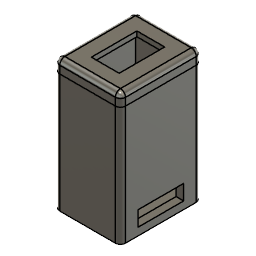
D_Case_sensor_temperatura (Autodesk Fusion 360 design; units mm, degrees)
Autodesk Fusion 360 part; units mm, degrees
sketch "Esboço1" plane through (0, 0, 0) normal (0, 1, 0) x (1, 0, 0)
  line L0 (11, -16) -> (-11, -16)
  line L1 (-13, -14) -> (-13, 14)
  line L2 (-11, 16) -> (11, 16)
  line L3 (13, 14) -> (13, -14)
  line L4 (13, -16) -> (-13, 16) construction
  line L5 (-13, -16) -> (13, 16) construction
  line L6 (10, -13) -> (-10, -13)
  line L7 (-10, -13) -> (-10, 13)
  line L8 (-10, 13) -> (10, 13)
  line L9 (10, 13) -> (10, -13)
  line L10 (10, -13) -> (-10, 13) construction
  line L11 (-10, -13) -> (10, 13) construction
  arc A0 (-11, 16) -> (-13, 14) centre (-11, 14) ccw
  arc A1 (13, 14) -> (11, 16) centre (11, 14) ccw
  arc A2 (11, -16) -> (13, -14) centre (11, -14) ccw
  arc A3 (-13, -14) -> (-11, -16) centre (-11, -14) ccw
  line L12 (0, 0) -> (-11.5, 0)
  line L13 (0, 0) -> (11.5, 0)
  line L14 (-10.75, -11.5) -> (-12.25, -11.5)
  line L15 (-12.25, -11.5) -> (-12.25, 11.5)
  line L16 (-12.25, 11.5) -> (-10.75, 11.5)
  line L17 (-10.75, 11.5) -> (-10.75, -11.5)
  line L18 (-10.75, -11.5) -> (-12.25, 11.5) construction
  line L19 (-12.25, -11.5) -> (-10.75, 11.5) construction
  line L20 (0, 0) -> (0, -14.5)
  line L21 (8.5, -15.25) -> (-8.5, -15.25)
  line L22 (-8.5, -15.25) -> (-8.5, -13.75)
  line L23 (-8.5, -13.75) -> (8.5, -13.75)
  line L24 (8.5, -13.75) -> (8.5, -15.25)
  line L25 (8.5, -15.25) -> (-8.5, -13.75) construction
  line L26 (-8.5, -15.25) -> (8.5, -13.75) construction
  line L27 (10.75, 11.5) -> (10.75, -11.5)
  line L28 (12.25, -11.5) -> (12.25, 11.5)
  line L29 (10.75, -11.5) -> (12.25, 11.5) construction
  line L30 (12.25, -11.5) -> (10.75, 11.5) construction
  line L31 (12.25, 11.5) -> (10.75, 11.5)
  line L32 (10.75, -11.5) -> (12.25, -11.5)
  line L33 (-8.5, 15.25) -> (-8.5, 13.75)
  line L34 (-8.5, 15.25) -> (8.5, 13.75) construction
  line L35 (8.5, 15.25) -> (-8.5, 13.75) construction
  line L36 (-8.5, 13.75) -> (8.5, 13.75)
  line L37 (8.5, 15.25) -> (-8.5, 15.25)
  line L38 (8.5, 13.75) -> (8.5, 15.25)
  point P0 (-11.5, 0)
  point P1 (0, -14.5)
  dimension "d1" = 26
  dimension "d2" = 32
  dimension "d3" = 20
  dimension "d4" = 26
  dimension "d5" = 2
  dimension "d6" = 2
  dimension "d7" = 11.5
  dimension "d8" = 11.5
  dimension "d9" = 1.5
  dimension "d10" = 23
  dimension "d11" = 14.5
  dimension "d12" = 17
  dimension "d13" = 1.5
  constraint horizontal L0
  constraint perpendicular L0 L1
  constraint parallel L0 L2
  constraint parallel L1 L3
  constraint coincident L4 L12.start
  constraint coincident L5 L12.start
  constraint coincident L12.start L13.start
  constraint horizontal L6
  constraint perpendicular L6 L7
  constraint parallel L6 L8
  constraint parallel L7 L9
  constraint coincident L10 L12.start
  constraint coincident L11 L12.start
  constraint coincident L4.end L2
  constraint coincident L4.end L1
  constraint tangent L2 A0
  constraint tangent L1 A0
  constraint coincident L5.end L2
  constraint coincident L5.end L3
  constraint tangent L2 A1
  constraint tangent L3 A1
  constraint coincident L4.start L3
  constraint coincident L4.start L0
  constraint tangent L3 A2
  constraint tangent L0 A2
  constraint equal A1 A2
  constraint coincident L5.start L0
  constraint coincident L5.start L1
  constraint tangent L0 A3
  constraint tangent L1 A3
  constraint equal A1 A3
  constraint perpendicular L7 L12
  constraint perpendicular L9 L13
  constraint horizontal L14
  constraint perpendicular L14 L15
  constraint parallel L14 L16
  constraint parallel L15 L17
  constraint coincident L18 P0
  constraint coincident L19 P0
  constraint coincident P0 L12.end
  constraint perpendicular L0 L20
  constraint horizontal L21
  constraint perpendicular L21 L22
  constraint parallel L21 L23
  constraint parallel L22 L24
  constraint coincident L25 P1
  constraint coincident L26 P1
  constraint coincident P1 L20.end
  constraint symmetric L14.start L20 L27.end
  constraint symmetric L14.end L20 L28.start
  constraint symmetric L15.end L20 L28.end
  constraint symmetric L16.end L20 L27.start
  constraint symmetric L12 L21.start L35.start
  constraint symmetric L12 L21.end L33.start
  constraint symmetric L12 L22.end L33.end
  constraint symmetric L12 L23.end L34.end
  measures "d1" distance of L4.end L5.end
  measures "d2" distance of L5.start L4.end
  measures "d3" distance of L7.end L8.end
  measures "d4" distance of L6.end L7.end
  measures "d5" radius of A0
  measures "d6" radius of A1
  measures "d7" distance of L12.start P0
  measures "d8" distance of L12.start L13.end
  measures "d9" distance of L15.end L16.end
  measures "d10" distance of L14.end L15.end
  measures "d11" distance of L12.start P1
  measures "d12" distance of L22.end L23.end
  measures "d13" distance of L21.end L22.end
extrude "Extrusão1" add sketch "Esboço1" against normal blind 47 contours L0 L1 L2 L3 A0 A1 A2 A3 | L14 L15 L16 L17 | L21 L22 L23 L24 | L27 L28 L31 L32 | L33 L36 L37 L38 makes body 1
sketch "Esboço2" plane through (0, 0, 0) normal (0, 1, 0) x (1, 0, 0)
extrude "Extrusão2" cut sketch "Esboço1" against normal blind 3 contours L14 L15 L16 L17 | L21 L22 L23 L24 | L27 L28 L31 L32 | L33 L36 L37 L38 bodies 1
copy_body "Corpo -> Componente1" bodies 1 removing the originals makes body 2 in component "Case_Temperatura"
ref_plane "Plano de trabalho1" through (0, 3, 0) normal (0, 1, 0) x (0, 0, 1)
sketch "Esboço3" plane through (0, 3, 0) normal (0, 1, 0) x (1, 0, 0)
ref_plane "Plano de trabalho2" through (0, 3, 0) normal (0, 1, 0) x (1, 0, 0)
sketch "Esboço4" plane through (0, 3, 0) normal (0, 1, 0) x (1, 0, 0)
extrude "Extrusão1'" add sketch "Esboço1" along normal blind 5 separate body contours L0 L1 L2 L3 A0 A1 A2 A3 | L14 L15 L16 L17 | L21 L22 L23 L24 | L27 L28 L31 L32 | L33 L36 L37 L38 makes body 3 in component "Tampa_Temperatura"
sketch "Esboço5" plane through (0, 5, 0) normal (0, 1, 0) x (-1, 0, 0)
  line L0 (10, -13) -> (-10, -13)
  line L1 (-10, -13) -> (-10, 13)
  line L2 (-10, 13) -> (10, 13)
  line L3 (10, 13) -> (10, -13)
  arc A0 (11, -16) -> (13, -14) centre (11, -14) ccw
  line L4 (13, -14) -> (13, 14)
  arc A1 (13, 14) -> (11, 16) centre (11, 14) ccw
  line L5 (11, 16) -> (-11, 16)
  arc A2 (-11, 16) -> (-13, 14) centre (-11, 14) ccw
  line L6 (-13, 14) -> (-13, -14)
  arc A3 (-13, -14) -> (-11, -16) centre (-11, -14) ccw
  line L7 (-11, -16) -> (11, -16)
extrude "Extrusão2'" add sketch "Esboço5" against normal blind 2 contours L0 L1 L2 L3 bodies 3 in component "Tampa_Temperatura"
sketch "Esboço6" plane through (0, -47, 0) normal (0, -1, 0) x (1, 0, 0)
  line L0 (10, -13) -> (-10, -13)
  line L1 (-10, -13) -> (-10, 13)
  line L2 (-10, 13) -> (10, 13)
  line L3 (10, 13) -> (10, -13)
  arc A0 (-13, -14) -> (-11, -16) centre (-11, -14) ccw
  line L4 (-11, -16) -> (11, -16)
  arc A1 (11, -16) -> (13, -14) centre (11, -14) ccw
  line L5 (13, -14) -> (13, 14)
  arc A2 (13, 14) -> (11, 16) centre (11, 14) ccw
  line L6 (11, 16) -> (-11, 16)
  arc A3 (-11, 16) -> (-13, 14) centre (-11, 14) ccw
  line L7 (-13, 14) -> (-13, -14)
extrude "Extrusão1''" add sketch "Esboço6" against normal blind 2 contours L0 L1 L2 L3 bodies 2 in component "Case_Temperatura"
extrude "Extrusão3" add sketch "Esboço1" against normal blind 2 contours L14 L15 L16 L17 | L21 L22 L23 L24 | L27 L28 L31 L32 | L33 L36 L37 L38 bodies 3 in component "Tampa_Temperatura"
sketch "Esboço7" plane through (0, 5, 0) normal (0, 1, 0) x (-1, 0, 0)
  arc A0 (11, -16) -> (13, -14) centre (11, -14) ccw
  line L0 (13, -14) -> (13, 14)
  arc A1 (13, 14) -> (11, 16) centre (11, 14) ccw
  line L1 (11, 16) -> (-11, 16)
  arc A2 (-11, 16) -> (-13, 14) centre (-11, 14) ccw
  line L2 (-13, 14) -> (-13, -14)
  arc A3 (-13, -14) -> (-11, -16) centre (-11, -14) ccw
  line L3 (-11, -16) -> (11, -16)
  line L4 (-5.5, 9) -> (5.5, 9)
  line L5 (5.5, 9) -> (5.5, -9)
  line L6 (5.5, -9) -> (-5.5, -9)
  line L7 (-5.5, -9) -> (-5.5, 9)
  line L8 (-5.5, 9) -> (5.5, -9) construction
  line L9 (5.5, 9) -> (-5.5, -9) construction
  dimension "d29" = 11
  dimension "d30" = 18
  constraint horizontal L4
  constraint perpendicular L4 L5
  constraint parallel L4 L6
  constraint parallel L5 L7
  constraint coincident L8 origin
  constraint coincident L9 origin
  measures "d29" distance of L5.end L6.end
  measures "d30" distance of L4.end L5.end
extrude "Extrusão4" cut sketch "Esboço7" against normal blind 2 contours L4 L5 L6 L7 bodies 3 in component "Tampa_Temperatura"
fillet "Arredondamento1" radius 2 8 edges at (0, 5, 16) (12.4142, 5, 15.4142) (13, 5, 0) (12.4142, 5, -15.4142) (0, 5, -16) (-12.4142, 5, -15.4142) (-13, 5, 0) (-12.4142, 5, 15.4142) on bodies 3 in component "Tampa_Temperatura"
sketch "Esboço8" plane through (13, 0, 0) normal (1, 0, 0) x (0, 0, -1)
  line L0 (14, 0) -> (-14, 0)
  line L1 (-14, 0) -> (-14, -47)
  line L2 (-14, -47) -> (14, -47)
  line L3 (14, -47) -> (14, 0)
  line L4 (0, -47) -> (0, -44)
  line L5 (0, -44) -> (9, -44)
  line L6 (9, -44) -> (9, -38)
  line L7 (9, -38) -> (0, -38)
  line L8 (0, -38) -> (0, -44)
  line L9 (0, -44) -> (-9, -44)
  line L10 (-9, -44) -> (-9, -38)
  line L11 (-9, -38) -> (0, -38)
  dimension "d35" = 3
  dimension "d36" = 9
  dimension "d37" = 6
  constraint midpoint L2 L4.start
  constraint perpendicular L2 L4
  constraint horizontal L5
  constraint vertical L6
  constraint horizontal L7
  constraint vertical L8
  constraint symmetric L4.end L8 L5.start
  constraint symmetric L5.end L8 L9.end
  constraint symmetric L6.end L8 L10.end
  constraint symmetric L7.end L8 L11.end
  measures "d35" distance of L4.start L4.end
  measures "d36" distance of L4.end L5.end
  measures "d37" distance of L4.end L7.end
extrude "Extrusão2''" cut sketch "Esboço8" against normal blind 3 contours L5 L6 L7 L8 | L8 L9 L10 L11 bodies 2 in component "Case_Temperatura"
component "Tampa_Temperatura" placed x (1, 0, 0) y (0, 1, 0) z (0, 0, 1) at (0, 0, 0)
component "Case_Temperatura" placed x (1, 0, 0) y (0, 1, 0) z (0, 0, 1) at (0, 0, 0)
